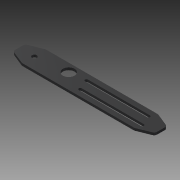
# Autodesk Inventor part: collecive_support_2
Saved by Autodesk Inventor 2015 (Build 190159000, 159)
## iProperties
Created: 2022-11-07
Part Number: collecive_support_2
Material: Generic
Document SubType Name: Modeling
Designer: Pavel Brodský
Density: 1 g/cm^3
Appearance: Default
Author: Pavel Brodský
Autodesk Inventor part; units mm, degrees
ref_plane "YZ Plane" through (0, 0, 0) normal (1, 0, 0) x (0, 1, 0)
ref_plane "XZ Plane" through (0, 0, 0) normal (0, 1, 0) x (-1, 0, 0)
ref_plane "XY Plane" through (0, 0, 0) normal (0, 0, 1) x (1, 0, 0)
sketch "Náčrt1" plane through (0, 0, 0) normal (0, 0, 1) x (1, 0, 0)
  line L0 (25.9629, 0) -> (214.0371, 0)
  line L1 (240, 13.3852) -> (240, 26.6148)
  line L2 (214.0371, 40) -> (25.9629, 40)
  line L3 (0, 26.6148) -> (0, 13.3852)
  line L4 (24.106, 39.6424) -> (3.143, 31.2572)
  line L5 (24.106, 0.3576) -> (3.143, 8.7428)
  line L6 (215.894, 0.3576) -> (236.857, 8.7428)
  line L7 (215.894, 39.6424) -> (236.857, 31.2572)
  arc A0 (25.9629, 40) -> (24.106, 39.6424) centre (25.9629, 35) ccw
  arc A1 (3.143, 31.2572) -> (0, 26.6148) centre (5, 26.6148) ccw
  arc A2 (0, 13.3852) -> (3.143, 8.7428) centre (5, 13.3852) ccw
  arc A3 (24.106, 0.3576) -> (25.9629, 0) centre (25.9629, 5) ccw
  arc A4 (236.857, 8.7428) -> (240, 13.3852) centre (235, 13.3852) ccw
  arc A5 (214.0371, 0) -> (215.894, 0.3576) centre (214.0371, 5) ccw
  arc A6 (240, 26.6148) -> (236.857, 31.2572) centre (235, 26.6148) ccw
  arc A7 (215.894, 39.6424) -> (214.0371, 40) centre (214.0371, 35) ccw
  arc A8 (210, 26.5) -> (210, 31.5) centre (210, 29) ccw
  arc A9 (105, 31.5) -> (105, 26.5) centre (105, 29) ccw
  arc A10 (112.5, 13.5) -> (112.5, 8.5) centre (112.5, 11) ccw
  arc A11 (217.5, 8.5) -> (217.5, 13.5) centre (217.5, 11) ccw
  line L8 (105, 31.5) -> (210, 31.5)
  line L9 (105, 26.5) -> (210, 26.5)
  line L10 (112.5, 13.5) -> (217.5, 13.5)
  line L11 (112.5, 8.5) -> (217.5, 8.5)
  circle A12 centre (78, 26) radius 10
  circle A13 centre (26, 20) radius 4
  point P0 (0, 0)
  point P1 (240, 40)
  point P2 (240, 0)
  point P3 (0, 40)
  point P4 (25, 40)
  point P5 (0, 30)
  point P6 (25, 0)
  point P7 (0, 10)
  point P8 (215, 0)
  point P9 (240, 10)
  point P10 (215, 40)
  point P11 (240, 30)
  dimension "d0" = 40
  dimension "d1" = 240
  dimension "d2" = 25
  dimension "d3" = 10
  dimension "d4" = 25
  dimension "d5" = 10
  dimension "d6" = 25
  dimension "d7" = 10
  dimension "d8" = 25
  dimension "d9" = 10
  dimension "d10" = 5
  dimension "d11" = 5
  dimension "d12" = 5
  dimension "d13" = 5
  dimension "d14" = 5
  dimension "d15" = 105
  dimension "d16" = 105
  dimension "d17" = 30
  dimension "d18" = 22.5
  dimension "d19" = 11
  dimension "d20" = 11
  dimension "d21" = 8
  dimension "d22" = 20
  dimension "d23" = 14
  dimension "d24" = 78
  dimension "d25" = 20
  dimension "d26" = 26
  constraints: 24 end point, 24 point on circle, 24 point on line, 24 tangent, 14 centre point, 7 equal radius, 2 horizontal alignment, 2 parallel, 1 horizontal, 1 perpendicular
  measures "d0" distance between parallel lines of L0 L2
  measures "d1" distance between parallel lines of L1 L3
  measures "d2" distance of point (25, 40) point (0, 40)
  measures "d3" distance of point (0, 30) point (0, 40)
  measures "d4" distance of point (25, 0) point (0, 0)
  measures "d5" distance of point (0, 10) point (0, 0)
  measures "d6" distance of point (215, 0) point (240, 0)
  measures "d7" distance of point (240, 10) point (240, 0)
  measures "d8" distance of point (215, 40) point (240, 40)
  measures "d9" distance of point (240, 30) point (240, 40)
  measures "d10" radius of A0
  measures "d11" diameter of A8
  measures "d12" diameter of A9
  measures "d13" diameter of A10
  measures "d14" diameter of A11
  measures "d15" distance of A8.centre A9.centre
  measures "d16" distance of A10.centre A11.centre
  measures "d17" distance from line of L1 A8.centre
  measures "d18" distance from line of L1 A11.centre
  measures "d19" distance from line of L2 A8.centre
  measures "d20" distance from line of L0 A11.centre
  measures "d21" diameter of A13
  measures "d22" diameter of A12
  measures "d23" distance from line of L2 A12.centre
  measures "d24" distance from line of L3 A12.centre
  measures "d25" distance from line of L2 A13.centre
  measures "d26" distance from line of L3 A13.centre
extrude "Vysunutí1" add sketch "Náčrt1" along normal blind 4
equation "\"d4\" = d2"
equation "\"d5\" = d3"
equation "\"d6\" = d2"
equation "\"d7\" = d3"
equation "\"d8\" = d2"
equation "\"d9\" = d3"
